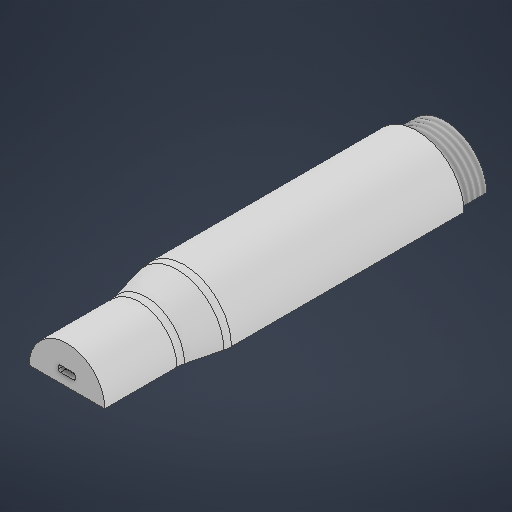
# Autodesk Inventor part: Blender_Upper Housing2
Saved by Autodesk Inventor 2027.1 (Build 311270010, 270A)
## iProperties
Created: 2026-10-20
Part Number: Blender_Upper Housing2
Material: Generic
Document SubType Name: Modeling
Designer: MSIPC
Density: 1 g/cm^3
Appearance: Default
Author: MSIPC
Autodesk Inventor part; units mm, degrees
ref_plane "YZ Plane" through (0, 0, 0) normal (1, 0, 0) x (0, 1, 0)
sketch "Sketch1" plane through (0, 0, 0) normal (0, 1, 0) x (-1, 0, 0)
  line L0 (-25, 15) -> (-25, 138.0083)
  line L1 (-24.5589, 141.6192) -> (-20.4411, 158.2215)
  line L2 (-20, 161.8324) -> (-20, 200)
  line L3 (-20, 200) -> (-17, 200)
  line L4 (0, 200) -> (0, 0)
  arc A0 (-20.4411, 158.2215) -> (-20, 161.8324) centre (-35, 161.8324) ccw
  arc A1 (-24.5589, 141.6192) -> (-25, 138.0083) centre (-10, 138.0083) ccw
  line L5 (-22, 138) -> (-22, 18)
  line L6 (-17, 197) -> (-17, 161.8324)
  arc A2 (-17.5293, 157.4993) -> (-17, 161.8324) centre (-35, 161.8324) ccw
  line L7 (-17.5293, 157.4993) -> (-21.6471, 140.897)
  arc A3 (-21.6471, 140.897) -> (-22, 138) centre (-10, 138.0083) ccw
  line L8 (-22, 18) -> (-19, 18)
  line L9 (-25, 15) -> (-22, 15)
  line L10 (-22, 15) -> (-22, 0)
  line L11 (-22, 0) -> (-19, 0)
  line L12 (-19, 2) -> (-20.5, 2)
  line L13 (-20.5, 2) -> (-20.5, 2.5)
  line L14 (-20.5, 2.5) -> (-19, 2.5)
  line L15 (-19, 18) -> (-19, 2.5)
  line L16 (-19, 2) -> (-19, 0)
  line L17 (-17, 200) -> (0, 200)
  line L18 (-17, 197) -> (0, 197)
  point P0 (-25, 139.8407)
  point P1 (-20, 160)
  point P2 (-8.5, 200)
  point P3 (-8.5, 197)
  dimension "d2" = 20
  dimension "d3" = 200
  dimension "d4" = 40
  dimension "d5" = 15
  dimension "d6" = 15
  dimension "d7" = 3
  dimension "d9" = 3
  dimension "d10" = 3
  dimension "d13" = 3
  dimension "d15" = 15
  dimension "d17" = 22
  dimension "d18" = 120
  dimension "d19" = 25
  dimension "d86" = 1.5
  dimension "d87" = 0.5
  dimension "d90" = 2
  dimension "d91" = 13.93
  dimension "d92" = 3
  constraints: 38 end point, 8 point on circle, 5 perpendicular, 5 point on line, 4 centre point, 4 horizontal, 4 tangent, 3 parallel, 2 midpoint, 2 vertical, 2 other
  measures "d2" distance of L2.end L4.start
  measures "d3" distance of L4.start L4.end
  measures "d4" distance of point (-20, 160) L2.end
  measures "d5" radius of A0
  measures "d6" radius of A1
  measures "d7" distance between parallel lines of L0 L5
  measures "d9" distance between parallel lines of L2 L6
  measures "d10" distance between parallel lines of L7 L1
  measures "d13" distance between parallel lines of L8 L9
  measures "d15" distance from line of L4.end L9
  measures "d17" distance between parallel lines of L4 L10
  measures "d18" distance of L5.start L5.end
  measures "d19" distance between parallel lines of L4 L0
  measures "d86" distance of L13.end L14.end
  measures "d87" distance of L12.end L13.end
  measures "d90" distance from line of L12 L4.end
  measures "d91" angle of L4 L7
  measures "d92" distance of point (-8.5, 200) point (-8.5, 197)
revolve "Revolution1" add sketch "Sketch1" angle 360 about axis through (0, 0, 200) along (0, 0, -1)
thread "Thread1" size "M45x3" class "6g" standard "ANSI Metric M Profile" full length
ref_plane "Work Plane1" through (0, -25, 76.5041) normal (0, 1, 0) x (-1, 0, 0)
sketch "Sketch4" plane through (0, -25, 76.5041) normal (0, 1, 0) x (-1, 0, 0)
  circle A0 centre (0, 35.7219) radius 10
  point P0 (0, -76.5041)
  dimension "d22" = 20
  constraints: 1 centre point
  measures "d22" diameter of A0
extrude "Extrusion1" add sketch "Sketch4" along normal up to surface round surface about axis through (0, 0, 78) along (0, 0, -1) radius 22 far side no
fillet "Fillet1" radius 2 3 edges at (-7.6112, -23.8132, 105.7399) (-7.6096, -23.8137, 118.714) (10, -22.9129, 112.2182)
sketch "Sketch5" plane through (0, 0, 200) normal (0, 0, 1) x (1, 0, 0)
  line L0 (32.7482, 0) -> (-33.1433, 0)
  line L1 (-33.1433, 0) -> (-33.1433, -28.5183)
  line L2 (-33.1433, -28.5183) -> (32.7482, -28.5183)
  line L3 (32.7482, -28.5183) -> (32.7482, 0)
  point P0 (0, 0)
  constraints: 8 end point, 2 parallel, 1 horizontal, 1 perpendicular
extrude "Extrusion2" cut sketch "Sketch5" against normal blind 219
sketch "Sketch6" plane through (-25, 0, 15) normal (0, -1, 0) x (1, 0, 0)
  line L0 (3, 123) -> (3, 3) projected
  line L1 (3, 28.3) -> (16.22, 28.3)
  line L2 (16.22, 28.3) -> (16.22, 26.8)
  line L3 (16.22, 26.8) -> (3, 26.8)
  line L4 (3, 26.8) -> (3, 28.3)
  line L5 (3, 3) -> (6, 3) projected
  line L6 (16.22, 28.3) -> (10.22, 28.3)
  line L7 (10.22, 28.3) -> (10.22, 26.8)
  line L8 (10.22, 26.8) -> (16.22, 26.8)
  line L9 (16.22, 26.8) -> (16.22, 28.3)
  point P0 (25, -15)
  point P1 (16.22, 27.55)
  point P2 (4.5, 3)
  point P3 (3, 26.8)
  dimension "d28" = 1.5
  dimension "d29" = 13.22
  dimension "d30" = 23.8
  dimension "d42" = 6
  constraints: 16 end point, 4 parallel, 2 horizontal, 2 midpoint, 2 perpendicular, 2 point on line
  measures "d28" distance between parallel lines of L1 L3
  measures "d29" distance from line of L0 point (16.22, 27.55)
  measures "d30" distance from line of point (4.5, 3) L3
  measures "d42" distance of L8.end L7.end
extrude "Extrusion3" add sketch "Sketch6" against normal up to surface round surface about axis through (0, 0, 78) along (0, 0, -1) radius 22 far side no
sketch "Sketch8" plane through (-25, 0, 15) normal (0, -1, 0) x (1, 0, 0)
  line L0 (16.22, 26.8) -> (16.22, 28.3) projected
  line L1 (3, 26.8) -> (16.22, 26.8) projected
  line L2 (16.22, 28.3) -> (8.22, 28.3)
  line L3 (8.22, 28.3) -> (8.22, 26.8)
  line L4 (8.22, 26.8) -> (16.22, 26.8)
  line L5 (16.22, 26.8) -> (16.22, 28.3)
  point P0 (25, -15)
  dimension "d43" = 8
  constraints: 8 end point, 2 parallel, 1 horizontal, 1 perpendicular, 1 point on line
  measures "d43" distance of L4.end L3.end
extrude "Extrusion4" add sketch "Sketch8" along normal blind 5
fillet "Fillet3" radius 2 3 edges at (-16.78, 0, 42.55) (-16.78, -5, 42.55) (-8.78, -5, 42.55)
sketch "Sketch9" plane through (-18.78, 0, 41.8) normal (0, 0, -1) x (-1, 0, 0)
  line L0 (-4, -5) -> (-8, -5) projected
  line L1 (-10, 20.172) -> (-10, -3) projected
  point P0 (-18.78, 0)
  point P1 (-7.28, 0)
  dimension "d47" = 5
  dimension "d55" = 2.72
  measures "d47" distance from line of L0 point (-7.28, 0)
  measures "d55" distance from line of L1 point (-7.28, 0)
hole "Hole2" at (-11.5, 0, 41.8) direction (0, 0, 1) diameter 1.2 depth 136.95 tip angle 118
mirror "Mirror2" about plane through (0, 0, 0) normal (1, 0, 0) of "Extrusion3", "Extrusion4", "Fillet3", "Hole2"
ref_plane "Work Plane2" through (25, 15, 15) normal (0, -1, 0) x (1, 0, 0)
sketch "Sketch12" plane through (25, 15, 15) normal (0, -1, 0) x (1, 0, 0)
  line L0 (-25, -15) -> (-25, 184.9917)
  circle A0 centre (-30.5, 43.3) radius 0.35
  line L1 (-29, 41.8) -> (-32, 41.8)
  line L2 (-32, 41.8) -> (-32, 44.8)
  line L3 (-32, 44.8) -> (-29, 44.8)
  line L4 (-29, 44.8) -> (-29, 41.8)
  line L5 (-29, 41.8) -> (-32, 44.8) construction
  line L6 (-32, 41.8) -> (-29, 44.8) construction
  circle A1 centre (-19.5, 43.3) radius 0.35
  line L7 (-21, 41.8) -> (-18, 41.8)
  line L8 (-18, 41.8) -> (-18, 44.8)
  line L9 (-18, 44.8) -> (-21, 44.8)
  line L10 (-21, 44.8) -> (-21, 41.8)
  line L11 (-21, 41.8) -> (-18, 44.8) construction
  line L12 (-18, 41.8) -> (-21, 44.8) construction
  dimension "d76" = 0.7
  dimension "d77" = 5.5
  dimension "d79" = 3
  dimension "d80" = 3
  constraints: 26 end point, 5 symmetric about line, 2 centre point, 2 midpoint, 2 parallel, 1 horizontal, 1 perpendicular, 1 other
  measures "d76" diameter of A0
  measures "d77" distance from line of L0 A0.centre
  measures "d79" distance of L2.end L3.end
  measures "d80" distance of L1.end L2.end
extrude "Extrusion7" add sketch "Sketch12" against normal up to surface round surface about axis through (0, 0, 78) along (0, 0, -1) radius 22 far side no
pattern_linear "Rectangular Pattern1" count 2 spacing 58.5 along (0, 0, 1) of "Extrusion7"
sketch "Sketch13" plane through (-20, 0, 200) normal (0, -1, 0) x (1, 0, 0)
  line L0 (-2, -158.2) -> (-2, -182) projected
  line L1 (-2, -174) -> (1, -174)
  line L2 (1, -174) -> (1, -177)
  line L3 (1, -177) -> (-2, -177)
  line L4 (-2, -177) -> (-2, -174)
  line L5 (-2, -182) -> (1, -182) projected
  point P0 (20, -200)
  point P1 (-2, -177)
  dimension "d93" = 3
  dimension "d94" = 3
  dimension "d95" = 5
  constraints: 8 end point, 2 parallel, 1 horizontal, 1 perpendicular, 1 point on line
  measures "d93" distance of L2.end L3.end
  measures "d94" distance of L1.end L2.end
  measures "d95" distance between parallel lines of L5 L3
extrude "Extrusion8" add sketch "Sketch13" against normal up to surface round surface about axis through (0, 0, 78) along (0, 0, -1) radius 22 far side no
sketch "Sketch14" plane through (-20, 0, 200) normal (0, -1, 0) x (1, 0, 0)
  circle A0 centre (-0.5, -175.5) radius 0.5
  line L0 (-2, -177) -> (1, -177) projected
  line L1 (1, -177) -> (1, -174) projected
  point P0 (20, -200)
  dimension "d98" = 1
  dimension "d99" = 1.5
  dimension "d100" = 1.5
  constraints: 1 centre point
  measures "d98" diameter of A0
  measures "d99" distance from line of L0 A0.centre
  measures "d100" distance from line of L1 A0.centre
extrude "Extrusion9" cut sketch "Sketch14" against normal blind 2
pattern_linear "Rectangular Pattern2" count 3 spacing 55 along (0, 0, 1) of "Extrusion8", "Extrusion9"
mirror "Mirror3" about plane through (0, 0, 0) normal (1, 0, 0) of "Extrusion9", "Extrusion8", "Rectangular Pattern2"
sketch "Sketch15" plane through (25, 15, 15) normal (0, -1, 0) x (1, 0, 0)
  line L0 (-17, 177) -> (-20, 177)
  line L1 (-20, 177) -> (-20, 174)
  line L2 (-20, 174) -> (-17, 174)
  line L3 (-17, 174) -> (-17, 177)
  line L4 (-8, 182) -> (-42, 182) projected
  circle A0 centre (-18.5, 175.5) radius 0.35
  line L5 (-30, 177) -> (-33, 177)
  line L6 (-33, 177) -> (-33, 174)
  line L7 (-33, 174) -> (-30, 174)
  line L8 (-30, 174) -> (-30, 177)
  circle A1 centre (-31.5, 175.5) radius 0.35
  line L9 (-8, 182) -> (-8, 171.717)
  line L10 (-17, 152) -> (-20, 152)
  line L11 (-20, 152) -> (-20, 149)
  line L12 (-20, 149) -> (-17, 149)
  line L13 (-17, 149) -> (-17, 152)
  circle A2 centre (-18.5, 150.5) radius 0.35
  line L14 (-30, 149) -> (-30, 152)
  circle A3 centre (-31.5, 150.5) radius 0.35
  line L15 (-30, 152) -> (-33, 152)
  line L16 (-33, 152) -> (-33, 149)
  line L17 (-33, 149) -> (-30, 149)
  point P0 (-25, -15)
  point P1 (-25, 182)
  dimension "d106" = 3
  dimension "d107" = 3
  dimension "d108" = 5
  dimension "d109" = 5
  dimension "d110" = 0.7
  dimension "d111" = 1.5
  dimension "d112" = 1.5
  dimension "d115" = 13
  dimension "d122" = 25
  constraints: 34 end point, 4 centre point, 2 horizontal, 2 parallel, 2 vertical, 1 midpoint, 1 perpendicular, 30 other
  measures "d106" distance of L2.end L1.end
  measures "d107" distance of L1.end L0.end
  measures "d108" distance between parallel lines of L4 L0
  measures "d109" distance from line of point (-25, 182) L1
  measures "d110" diameter of A0
  measures "d111" distance from line of L3 A0.centre
  measures "d112" distance from line of L0 A0.centre
  measures "d115" distance of L0.start L5.start
  measures "d122" distance of L1.end L11.end
extrude "Extrusion10" add sketch "Sketch15" against normal up to surface round surface about axis through (0, 0, 179.4162) along (0, 0, -1) radius 17 far side no
sketch "Sketch16" plane through (0, 0, 200) normal (0, 0, 1) x (1, 0, 0)
  line L0 (-3.47, 8.26) -> (3.47, 8.26)
  line L1 (4.47, 7.26) -> (4.47, 6)
  line L2 (3.47, 5) -> (-3.47, 5)
  line L3 (-4.47, 6) -> (-4.47, 7.26)
  line L4 (-4.47, 8.26) -> (4.47, 5) construction
  line L5 (4.47, 8.26) -> (-4.47, 5) construction
  line L6 (0, 0) -> (0, 6.63)
  line L7 (-20, 0) -> (20, 0) projected
  arc A0 (3.47, 5) -> (4.47, 6) centre (3.47, 6) ccw
  arc A1 (4.47, 7.26) -> (3.47, 8.26) centre (3.47, 7.26) ccw
  arc A2 (3.47, 5) -> (4.47, 6) centre (3.47, 6) ccw
  arc A3 (-4.47, 6) -> (-3.47, 5) centre (-3.47, 6) ccw
  arc A4 (-3.47, 8.26) -> (-4.47, 7.26) centre (-3.47, 7.26) ccw
  dimension "d129" = 3.26
  dimension "d130" = 8.94
  dimension "d131" = 5
  dimension "d132" = 1
  constraints: 14 end point, 10 point on circle, 10 point on line, 10 tangent, 5 centre point, 4 equal radius, 2 midpoint, 2 parallel, 1 horizontal, 1 perpendicular, 1 vertical
  measures "d129" distance of L5.end L4.start
  measures "d130" distance of L4.end L5.end
  measures "d131" distance between parallel lines of L7 L2
  measures "d132" radius of A0
extrude "Extrusion11" cut sketch "Sketch16" against normal up to surface (3 mm away)
body "Solid1"
